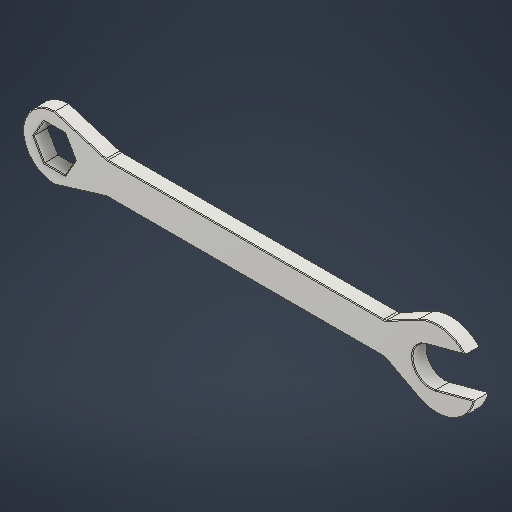
# Autodesk Inventor part: WR-016-200
Saved by Autodesk Inventor 2027 (Build 310192000, 192)
## iProperties
Created: 2026-11-07
Part Number: WR-016-200
Material: Steel AISI 6150
Description: 16 mm flat combination wrench - six-point ring / 15 deg open jaw
Document SubType Name: Modeling
Designer: Legion
Density: 7.85 g/cm^3
Appearance: Steel
Mass: 148.655 g
Surface Area: 91.7598 cm^2
Volume: 18.9369 cm^3
Elastic modulus reference: 210 GPa
Opening limits: 16.10 +0.05/-0.00 mm, both ends
Heat treatment: Quench and temper; target 44-48 HRC (design requirement)
Nominal wrench size: 16 mm
Finish: Satin nickel/chrome plate; openings sized after plating
Design status: Nominal flat-pattern design; no standard certification or torque rating
Poisson ratio reference: 0.30
Density reference: 7850 kg/m^3
Process: Drop forge, heat treat, machine / broach, deburr, plate
General tolerance: Linear +/-0.2 mm; angles +/-0.5 deg unless noted
Jaw angle: 15 deg in plane; ring offset 0 deg
Material specification: AISI 6150 chromium-vanadium steel
Author: Legion
Autodesk Inventor part; units mm, degrees
ref_plane "YZ Plane" through (0, 0, 0) normal (1, 0, 0) x (0, 1, 0)
ref_plane "XZ Plane" through (0, 0, 0) normal (0, 1, 0) x (-1, 0, 0)
ref_plane "XY Plane" through (0, 0, 0) normal (0, 0, 1) x (1, 0, 0)
sketch "Forging outline - 200 x 34 mm" plane through (0, 0, 0) normal (0, 0, 1) x (1, 0, 0)
  arc A0 (14, 14) -> (14, -14) centre (14, 0) ccw
  line L0 (14, -14) -> (37, -7)
  line L1 (37, -7) -> (160, -7)
  line L2 (160, -7) -> (175, -15)
  arc A1 (175, -15) -> (175, 15) centre (183, 0) ccw
  line L3 (175, 15) -> (160, 7)
  line L4 (160, 7) -> (37, 7)
  line L5 (37, 7) -> (14, 14)
  constraints: 12 end point, 4 point on circle, 2 centre point, 2 horizontal, 6 other
extrude "Forged blank - thickness" add sketch "Forging outline - 200 x 34 mm" along normal blind 6.5
sketch "16.10 AF six-point ring" plane through (0, 0, 0) normal (0, 0, 1) x (1, 0, 0)
  line L0 (23.2953, 0) -> (18.6477, 8.05)
  line L1 (18.6477, 8.05) -> (9.3523, 8.05)
  line L2 (9.3523, 8.05) -> (4.7047, 0)
  line L3 (4.7047, 0) -> (9.3523, -8.05)
  line L4 (9.3523, -8.05) -> (18.6477, -8.05)
  line L5 (18.6477, -8.05) -> (23.2953, 0)
  constraints: 12 end point, 2 horizontal, 4 other
extrude "Broached ring - 16.10 AF" cut sketch "16.10 AF six-point ring" along normal blind 6.5
sketch "Open jaw - 16.10 mm at 15 deg" plane through (0, 0, 0) normal (0, 0, 1) x (1, 0, 0)
  line L0 (182.1857, -8.5522) -> (223.7205, 2.5771)
  line L1 (223.7205, 2.5771) -> (219.5535, 18.1285)
  line L2 (219.5535, 18.1285) -> (178.0187, 6.9992)
  arc A0 (178.0187, 6.9992) -> (182.1857, -8.5522) centre (180.1022, -0.7765) ccw
  constraints: 6 end point, 2 point on circle, 1 centre point, 4 other
extrude "Milled open jaw - 15 deg" cut sketch "Open jaw - 16.10 mm at 15 deg" along normal blind 6.5
fillet "Shoulder transition R3" radius 3 4 edges at (37, 7, 3.25) (160, 7, 3.25) (160, -7, 3.25) (37, -7, 3.25)
chamfer "Edge break - 0.3 x 45 deg" distance 0.3 angle 45 44 edges at (37.0049, -7.0327, 0) (37.0049, -7.0327, 6.5) (98.3482, -7, 0) (98.3482, -7, 6.5) (159.9776, -7.0896, 0) (159.9776, -7.0896, 6.5) (167.8309, -11.1765, 0) (167.8309, -11.1765, 6.5) (159.9776, 7.0896, 0) (159.9776, 7.0896, 6.5) (98.3482, 7, 0) (98.3482, 7, 6.5) (37.0049, 7.0327, 0) (37.0049, 7.0327, 6.5) (25.2865, 10.565, 0) (25.2865, 10.565, 6.5) (172.3265, -2.86, 0) (172.3265, -2.86, 6.5) (186.6991, 9.3252, 6.5) (186.6991, 9.3252, 0) (190.8661, -6.2263, 0) (190.8661, -6.2263, 6.5) (190.0044, -15.49, 0) (25.2865, -10.565, 0) (0, 0, 0) (167.8309, 11.1765, 0) (185.7566, 16.775, 0) (20.9715, -4.025, 0) (20.9715, 4.025, 0) (14, 8.05, 0) (7.0285, 4.025, 0) (7.0285, -4.025, 0) (14, -8.05, 0) (190.0044, -15.49, 6.5) (20.9715, -4.025, 6.5) (14, -8.05, 6.5) (7.0285, -4.025, 6.5) (7.0285, 4.025, 6.5) (14, 8.05, 6.5) (20.9715, 4.025, 6.5) (167.8309, 11.1765, 6.5) (185.7566, 16.775, 6.5) (25.2865, -10.565, 6.5) (0, 0, 6.5)
equation "\"d2\" = Thickness"
equation "\"d13\" = Thickness"
equation "\"Thickness\" = 6.5"
body "Solid1"
